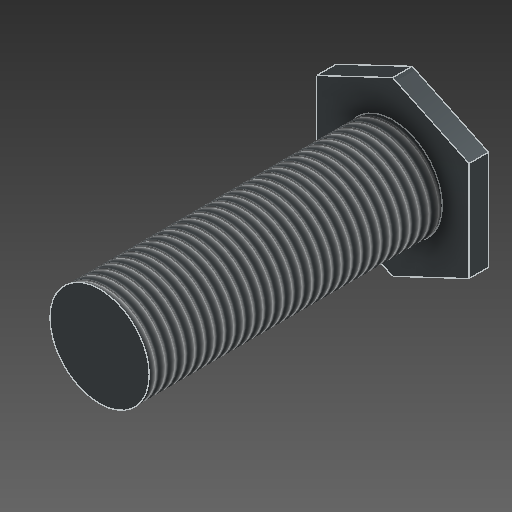
# Autodesk Inventor part: Bolt
Saved by Autodesk Inventor 2026.1 (Build 301233020, 233B)
## iProperties
Created: 2026-10-26
Part Number: Bolt
Material: Iron, Ductile
Document SubType Name: Modeling
Designer: YmCris
Density: 7.15 g/cm^3
Appearance: Iron Gray
Author: YmCris
Autodesk Inventor part; units mm, degrees
ref_plane "YZ Plane" through (0, 0, 0) normal (1, 0, 0) x (0, 1, 0)
ref_plane "XZ Plane" through (0, 0, 0) normal (0, 1, 0) x (-1, 0, 0)
ref_plane "XY Plane" through (0, 0, 0) normal (0, 0, 1) x (1, 0, 0)
sketch "Sketch1" plane through (0, 0, 0) normal (0, 0, 1) x (1, 0, 0)
  line L0 (-38.9529, 0.0471) -> (-38.9529, -25.4529)
  line L1 (39.0471, 0.0471) -> (39.0471, -25.4529)
  line L2 (-38.9529, 0.0471) -> (-38.9529, 25.5471)
  line L3 (39.0471, 0.0471) -> (39.0471, 25.5471)
  line L4 (39.0471, -25.4529) -> (-0.0266, -43.9879)
  line L5 (-0.0266, -43.9879) -> (-38.9529, -25.4529)
  line L6 (39.0471, 25.5471) -> (-0.0266, 44.082)
  line L7 (-0.0266, 44.082) -> (-38.9529, 25.5471)
  point P0 (0, 0)
  point P1 (0.0471, 0.0471)
  dimension "d0" = 25.5
  dimension "d1" = 51
  constraints: 16 end point, 1 vertical
  measures "d0" distance of L0.start L0.end
  measures "d1" distance of L3.end L1.end
extrude "Extrusion1" add sketch "Sketch1" along normal blind 10
sketch "Sketch3" plane through (0, 0, 10) normal (0, 0, 1) x (1, 0, 0)
  circle A0 centre (0, 0) radius 25.4
  dimension "d18" = 50.8
  constraints: 1 centre point, 1 coincident
  measures "d18" diameter of A0
extrude "Extrusion2" add sketch "Sketch3" along normal blind 150
thread "Thread3" size "M52x5" class "6g" standard "ANSI Metric M Profile" length 150
body "Solid1"
